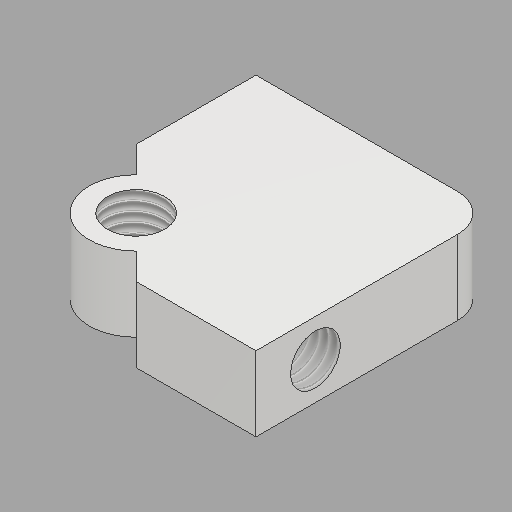
# Autodesk Inventor part: BT023_thutrn22_26
Saved by Autodesk Inventor 2025.3 (Build 293356000, 356)
## iProperties
Company: HTBLA Kaindorf
RuleStatus: InUse
Created: 2026-08-19
Part Number: BT023_thutrn22_26
Project: Biegeroboter
Material: ABS-Kunststoff
Description: halterung_getriebe
Document SubType Name: Modeling
Designer: thutrn22
Density: 1.06 g/cm^3
Appearance: Glatt - Weiß
Mass: 8.46084 g
Surface Area: 39.2995 cm^2
Volume: 7.98192 cm^3
AfterDocNew0: iProperties-Editor_aufrufen
Author: trist
Keywords: 2026
Autodesk Inventor part; units mm, degrees
ref_plane "YZ Plane" through (0, 0, 0) normal (1, 0, 0) x (0, 1, 0)
ref_plane "XZ Plane" through (0, 0, 0) normal (0, 1, 0) x (-1, 0, 0)
ref_plane "XY Plane" through (0, 0, 0) normal (0, 0, 1) x (1, 0, 0)
sketch "Skizze3" plane through (0, 0, 0) normal (0, 0, 1) x (1, 0, 0)
  line L0 (-22.4, 0) -> (22.4, 0) projected
  line L1 (0, -22.4) -> (0, 22.4) projected
  line L2 (-16, 16) -> (16, 16)
  line L3 (16, 16) -> (16, -16)
  line L4 (16, -16) -> (-16, -16)
  line L5 (-16, -16) -> (-16, 16)
  circle A0 centre (8.0381, -8.0381) radius 4.5
  line L6 (16, 0) -> (13.375, 0)
  line L7 (0, -16) -> (0, -13.375)
  line L8 (13.375, 0) -> (13.375, -13.375)
  line L9 (13.375, -13.375) -> (0, -13.375)
  point P0 (0, 0)
  dimension "d4" = 32
  dimension "d5" = 32
  dimension "d6" = 9
  dimension "d7" = 7.9619
  dimension "d8" = 7.9619
  dimension "d31" = 2.625
  dimension "d32" = 2.625
  constraints: 16 end point, 2 horizontal, 2 midpoint, 2 parallel, 2 point on line, 1 centre point, 1 coincident, 1 perpendicular, 1 vertical, 2 other
  measures "d4" distance of L3.end L4.end
  measures "d5" distance of L2.end L3.end
  measures "d6" diameter of A0
  measures "d7" distance from line of L4 A0.centre
  measures "d8" distance from line of L3 A0.centre
  measures "d31" distance of L6.start L6.end
  measures "d32" distance of L7.start L7.end
extrude "Extrusion3" add sketch "Skizze3" along normal blind 10 contours L0 L1 L2 L3 | L8 L9 L1 L0 | L0 L3 L4 L1 L9 L8 | L1 L4 L5 L0 | L0 L5 L2 L1 | A0
sketch "Skizze4" plane through (16, 16, 10) normal (0, 1, 0) x (1, 0, 0)
  line L0 (0, 10) -> (0, 0) projected
  line L1 (0, 0) -> (-32, 0) projected
  point P0 (-16, 10)
  point P1 (-7.962, 5)
  point P2 (-25.6, 0)
  dimension "d12" = 7.962
  dimension "d13" = 5
  measures "d12" distance from line of L0 point (-7.962, 5)
  measures "d13" distance from line of L1 point (-7.962, 5)
hole "Bohrung1" at (8.038, 16, 5) direction (0, -1, 0) diameter 6.647 depth 15 tip angle 118 thread size "M8x1.25" class "6H" standard "ISO Metric profile"
sketch "Skizze5" plane through (-16, -16, 0) normal (-1, 0, 0) x (0, 0, 1)
  line L0 (10, 32) -> (10, 0) projected
  line L1 (0, 0) -> (10, 0) projected
  point P0 (0, 16)
  point P1 (5, 7.962)
  point P2 (10, 25.6)
  dimension "d21" = 5
  dimension "d22" = 7.962
  measures "d21" distance from line of L0 point (5, 7.962)
  measures "d22" distance from line of L1 point (5, 7.962)
hole "Bohrung2" at (-16, -8.038, 5) direction (1, 0, 0) diameter 6.647 depth 15 tip angle 118 thread size "M8x1.25" class "6H" standard "ISO Metric profile"
fillet "Rundung2" radius 5 1 edges at (-16, 16, 5)
sketch "Skizze6" plane through (0, 0, 10) normal (0, 0, 1) x (1, 0, 0)
  line L0 (-16.1735, 0) -> (28.6265, 0)
  line L1 (0, -15.115) -> (0, 29.685)
  line L2 (-16, 16) -> (16, 16)
  line L3 (16, 16) -> (16, -16)
  line L4 (16, -16) -> (-16, -16)
  line L5 (-16, -16) -> (-16, 16)
  circle A0 centre (8.038, -8.038) radius 4.5
  line L6 (16, 0) -> (13.375, 0)
  line L7 (0, -16) -> (0, -13.375)
  line L8 (-25.1335, 0) -> (37.5865, 0) projected
  line L9 (0, -25.137) -> (0, 38.822) projected
  line L10 (8.038, -8.038) -> (14.3045, -8.038) construction
  circle A1 centre (8.038, -8.038) radius 6.2665
  line L11 (16, 0) -> (-0.0427, -16)
  point P0 (0, 0)
  point P1 (6.2265, 7.285)
  point P2 (28.6265, 0)
  point P3 (16, 0)
  point P4 (-16, 0)
  point P5 (3.5527, -12.4142)
  point P6 (0, -15.9575)
  point P7 (12.4261, -3.5644)
  dimension "d33" = 32
  dimension "d34" = 32
  dimension "d35" = 9
  dimension "d36" = 7.962
  dimension "d37" = 7.962
  dimension "d46" = 12.533
  constraints: 16 end point, 4 parallel, 2 centre point, 2 horizontal, 2 midpoint, 1 coincident, 1 perpendicular, 1 point on line, 10 other
  measures "d33" distance of L3.end L4.end
  measures "d34" distance of L2.end L3.end
  measures "d35" diameter of A0
  measures "d36" distance from line of L4 L10.start
  measures "d37" distance from line of L3 L10.start
  measures "d46" diameter of A1
extrude "Extrusion5" cut sketch "Skizze6" against normal blind 10 contours L3 L4 L7 L11 A1
hole "Bohrung3" at (8.0381, -8.0381, 0) direction (0, 0, 1) diameter 7.6468 end through all thread size "M9x1.25" class "6H" standard "ISO Metric profile"
